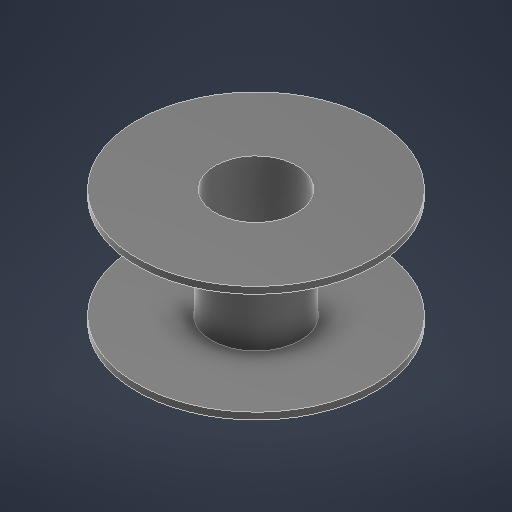
# Autodesk Inventor part: Coil spool
Saved by Autodesk Inventor 2026.2 (Build 302298010, 298A)
## iProperties
Created: 2026-10-04
Part Number: Coil spool
Material: Generisch
Document SubType Name: Modeling
Designer: denis
Mass: 15.9404 g
Surface Area: 193.208 cm^2
Volume: 15.9404 cm^3
Density: 1 g/cm^3
Appearance: Glatt - Schwarz
Author: denis
Autodesk Inventor part; units mm, degrees
ref_plane "YZ Plane" through (0, 0, 0) normal (1, 0, 0) x (0, 1, 0)
ref_plane "XZ Plane" through (0, 0, 0) normal (0, 1, 0) x (-1, 0, 0)
ref_plane "XY Plane" through (0, 0, 0) normal (0, 0, 1) x (1, 0, 0)
sketch "Skizze1" plane through (0, 0, 0) normal (0, 0, 1) x (1, 0, 0)
  line L0 (0, -24.5) -> (0, 24.5) construction
  line L1 (-7, 0) -> (42, 0) construction
  line L2 (10, 0) -> (35, 0)
  line L3 (10, 0) -> (35, 0) construction
  point P0 (0, 0)
  constraints: 4 end point, 2 horizontal, 1 collinear, 1 point on line
surface revolve "Rotationsfläche1" sketch "Skizze1" angle 360 about axis through (0, -10, 0) along (0, 1, 0) shown yes curves L2
sketch "Skizze2" plane through (0, 0, 0) normal (0, 1, 0) x (1, 0, 0)
  circle A0 centre (0, 0) radius 35 construction
  circle A1 centre (0, 0) radius 35
  circle A2 centre (0, 0) radius 11
  dimension "d16" = 22
  constraints: 2 centre point, 1 coincident, 1 concentric
  measures "d16" diameter of A2
extrude "Extrusion1" add sketch "Skizze2" against normal blind 2 contours A1 | A2
sketch "Skizze3" plane through (0, 0, 0) normal (0, 1, 0) x (1, 0, 0)
  circle A0 centre (0, 0) radius 10 construction
  circle A1 centre (0, 0) radius 12
  circle A2 centre (0, 0) radius 10
  dimension "d5" = 24
  constraints: 2 centre point, 2 coincident, 1 concentric
  measures "d5" diameter of A1
extrude "Extrusion2" add sketch "Skizze3" along normal blind 15 contours A1 | A2
sketch "Skizze4" plane through (0, 15, 0) normal (0, 1, 0) x (1, 0, 0)
  circle A0 centre (0, 0) radius 12 construction
  circle A1 centre (0, 0) radius 12
  dimension "d8" = 24
  constraints: 1 centre point, 1 coincident
  measures "d8" diameter of A1
extrude "Extrusion3" cut sketch "Skizze4" along normal mid plane 71.5
mirror "Spiegeln1" about plane through (0, 15, 0) normal (0, 1, 0) of "Extrusion1", "Extrusion2"
sketch "Skizze7" plane through (0, 32, 0) normal (0, 1, 0) x (1, 0, 0)
  circle A0 centre (0, 0) radius 35 construction
  circle A1 centre (0, 0) radius 12
  dimension "d17" = 24
  constraints: 1 centre point, 1 coincident
  measures "d17" diameter of A1
extrude "Extrusion6" cut sketch "Skizze7" against normal blind 23.5
sketch "Skizze8" plane through (0, 30, 0) normal (0, -1, 0) x (1, 0, 0)
  circle A0 centre (0, 0) radius 35 construction
  circle A1 centre (0, 0) radius 12
  circle A2 centre (0, 0) radius 13
  dimension "d20" = 24
  dimension "d21" = 26
  constraints: 2 centre point, 2 coincident
  measures "d20" diameter of A1
  measures "d21" diameter of A2
extrude "Extrusion7" add sketch "Skizze8" along normal up to surface (30 mm away)
